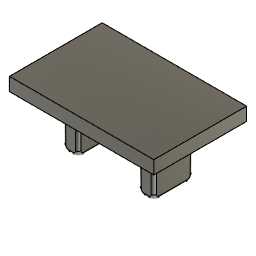
sadle_home_higher_1.02 (Autodesk Fusion 360 archive; units mm, degrees)
design "Kailh Choc Plug"
Autodesk Fusion 360 part; units mm, degrees
sketch "Sketch1" plane through (0, 0, 0) normal (0, 0, 1) x (1, 0, 0)
  line L0 (-3.45, 1.5) -> (-2.25, 1.5)
  line L1 (-2.25, 1.5) -> (-2.25, -1.5)
  line L2 (-2.25, -1.5) -> (-3.45, -1.5)
  line L3 (-3.45, -1.5) -> (-3.45, 1.5)
  line L4 (-5.45, -1.5) -> (-5.45, 1.5) construction
  line L5 (-3.45, 3.5) -> (-2.25, 3.5) construction
  line L6 (-3.45, 3.5) -> (-5.45, 3.5) construction
  line L7 (-5.45, 3.5) -> (-5.45, 1.5) construction
  line L8 (-5.45, 3.5) -> (5.45, 3.5)
  line L9 (5.45, 3.5) -> (5.45, -3.5)
  line L10 (5.45, -3.5) -> (-5.45, -3.5)
  line L11 (-5.45, -3.5) -> (-5.45, 3.5)
  line L12 (0, 1.75) -> (0, 22.5) construction
  line L13 (2.25, 1.5) -> (2.25, -1.5)
  line L14 (2.25, -1.5) -> (3.45, -1.5)
  line L15 (3.45, -1.5) -> (3.45, 1.5)
  line L16 (3.45, 1.5) -> (2.25, 1.5)
  line L17 (1.75, 0) -> (22.5, 0) construction
  dimension "d2" = 1.2
  dimension "d3" = 3
  dimension "d8" = -2
  dimension "d9" = -2
  dimension "d20" = 4.5
  dimension "d21" = 2
  dimension "d22" = 2
  dimension "d23" = 1.5
  constraint horizontal L0
  constraint vertical L1
  constraint horizontal L2
  constraint vertical L3
  constraint perpendicular L4 L6
  constraint perpendicular L6 L7
  constraint horizontal L8
  constraint perpendicular L8 L9
  constraint parallel L8 L10
  constraint parallel L9 L11
  constraint symmetric L0.start L12 L15.end
  constraint symmetric L0.end L12 L13.start
  constraint symmetric L1.end L12 L13.end
  constraint symmetric L2.end L12 L14.end
  measures "d2" distance of L1 L3
  measures "d3" distance of L0 L2
  measures "d20" distance of L1 L13
  measures "d21" distance of L9 L15
  measures "d22" distance of L10 L14
  measures "d23" distance of L0 L17
extrude "Extrude1" add sketch "Sketch1" against normal blind 3.8 draft -0.5 contours L0 L1 L2 L3 | L13 L14 L15 L16 makes body 1 at (-2.2611, 0.4889, -1.2667) makes body 2 at (3.4389, -0.4889, -1.2667)
extrude "Extrude2" add sketch "Sketch1" along normal blind 1 contours L0 L1 L2 L3 | L8 L9 L10 L11 | L13 L14 L15 L16 bodies 1 2
fillet "Fillet1" radius 0.2 4 edges at (-2.2666, 1.4834, -1.9) (-2.2666, -1.4834, -1.9) (-3.4334, 1.4834, -1.9) (-3.4334, -1.4834, -1.9) on bodies 1
fillet "Fillet1" radius 0.25 4 edges at (-2.85, -1.5, 0) (-2.25, 0, 0) (-2.85, 1.5, 0) (-3.45, 0, 0) on bodies 1
fillet "Fillet1" radius 0.2 4 edges at (-2.85, 1.4668, -3.8) (-2.2832, 0, -3.8) (-2.85, -1.4668, -3.8) (-3.4168, 0, -3.8) on bodies 1
fillet "Fillet1" radius 0.2 4 edges at (3.4168, 0, -3.8) (2.2832, 0, -3.8) (2.85, -1.4668, -3.8) (2.85, 1.4668, -3.8) on bodies 1
fillet "Fillet1" radius 0.2 4 edges at (3.4334, -1.4834, -1.9) (2.2666, -1.4834, -1.9) (2.2666, 1.4834, -1.9) (3.4334, 1.4834, -1.9) on bodies 1
fillet "Fillet1" radius 0.25 4 edges at (2.25, 0, 0) (2.85, -1.5, 0) (3.45, 0, 0) (2.85, 1.5, 0) on bodies 1
